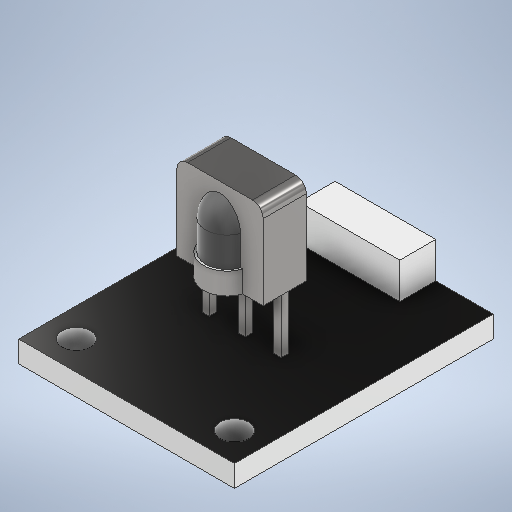
# Autodesk Inventor part: IR리모트 수광겐서
Saved by Autodesk Inventor 2025.3 (Build 293356030, 356C)
## iProperties
Created: 2025-09-11
Part Number: IR리모트 수광겐서
Material: ABS 플라스틱
Document SubType Name: Modeling
Designer: work
Density: 1.06 g/cm^3
Appearance: 매끄러움 - 흰색
Author: work
Autodesk Inventor part; units mm, degrees
ref_plane "YZ Plane" through (0, 0, 0) normal (1, 0, 0) x (0, 1, 0)
ref_plane "XZ Plane" through (0, 0, 0) normal (0, 1, 0) x (-1, 0, 0)
sketch "스케치1" plane through (0, 0, 0) normal (0, 1, 0) x (-1, 0, 0)
  line L0 (0, 0) -> (15, 0)
  line L1 (15, 0) -> (15, -18)
  line L2 (15, -18) -> (0, -18)
  line L3 (0, -18) -> (0, 0)
  dimension "d0" = 15
  dimension "d1" = 18
  constraints: 8 end point, 2 parallel, 1 horizontal, 1 perpendicular
  measures "d0" distance of L1.end L2.end
  measures "d1" distance of L0.end L1.end
extrude "돌출1" add sketch "스케치1" along normal blind 1.5
sketch "스케치2" plane through (0, 1.5, 0) normal (0, 1, 0) x (1, 0, 0)
  line L0 (-11, 15.5) -> (-4, 15.5)
  line L1 (-4, 15.5) -> (-4, 18)
  line L2 (-4, 18) -> (-11, 18)
  line L3 (-11, 18) -> (-11, 15.5)
  line L4 (0, 18) -> (-15, 18) projected
  point P0 (0, 0)
  point P1 (-7.5, 18)
  dimension "d4" = 7
  dimension "d5" = 2.5
  constraints: 8 end point, 2 midpoint, 2 parallel, 1 horizontal, 1 perpendicular
  measures "d4" distance of L2.end L1.end
  measures "d5" distance of L1.end L0.end
extrude "돌출2" add sketch "스케치2" along normal blind 2.5
sketch "스케치3" plane through (0, 1.5, 0) normal (0, 1, 0) x (1, 0, 0)
  line L0 (-10.25, 8) -> (-4.75, 8)
  line L1 (-4.75, 8) -> (-4.75, 8.5)
  line L2 (-4.75, 8.5) -> (-10.25, 8.5)
  line L3 (-10.25, 8.5) -> (-10.25, 8)
  line L4 (-15, 0) -> (0, 0) projected
  line L5 (-4, 18) -> (-11, 18) projected
  line L6 (-7.5, 18) -> (-7.5, 0) construction
  line L7 (-9.75, 8) -> (-9.75, 8.5)
  line L8 (-7.75, 8) -> (-7.75, 8.5)
  line L9 (-5.25, 8) -> (-5.25, 8.5)
  line L10 (-7.25, 8) -> (-7.25, 8.5)
  point P0 (-7.5, 8)
  point P1 (-4.75, 8.25)
  point P2 (-10.25, 8.25)
  dimension "d8" = 8
  dimension "d9" = 0.5
  dimension "d10" = 0.25
  dimension "d11" = 0.5
  dimension "d12" = 5.5
  constraints: 18 end point, 5 midpoint, 5 point on line, 4 symmetric about line, 3 perpendicular, 2 parallel, 1 horizontal
  measures "d8" distance between parallel lines of L4 L0
  measures "d9" distance of L2.end L0.start
  measures "d10" distance between parallel lines of L6 L8
  measures "d11" distance between parallel lines of L3 L7
  measures "d12" distance of point (-4.75, 8.25) point (-10.25, 8.25)
extrude "돌출3" add sketch "스케치3" along normal blind 4 contours L3 L2 L7 L0 | L8 L2 L10 L0 | L9 L2 L1 L0
sketch "스케치4" plane through (0, 5.5, 0) normal (0, 1, 0) x (1, 0, 0)
  line L0 (-10.5, 9.5) -> (-4.5, 9.5)
  line L1 (-4.5, 9.5) -> (-4.5, 6.5)
  line L2 (-4.5, 6.5) -> (-10.5, 6.5)
  line L3 (-10.5, 6.5) -> (-10.5, 9.5)
  line L4 (0, 18) -> (-15, 18) projected
  line L5 (-7.5, 18) -> (-7.5, 0) construction
  line L6 (-15, 0) -> (0, 0) projected
  line L7 (-7.25, 8.5) -> (-7.75, 8.5) projected
  point P0 (-7.5, 9.5)
  dimension "d15" = 6
  dimension "d16" = 3
  dimension "d17" = 1
  constraints: 10 end point, 3 midpoint, 2 parallel, 1 horizontal, 1 perpendicular, 1 point on line
  measures "d15" distance of L1.end L2.end
  measures "d16" distance of L0.end L1.end
  measures "d17" distance between parallel lines of L0 L7
extrude "돌출4" add sketch "스케치4" along normal blind 6
ref_plane "작업 평면1" through (-7.5, 5.5, -6.5) normal (1, 0, 0) x (0, 0, -1)
sketch "스케치5" plane through (-7.5, 5.5, -6.5) normal (1, 0, 0) x (0, 0, -1)
  line L0 (0, 0) -> (3, 0) projected
  line L1 (0.5, 0) -> (0.5, 5.5)
  arc A0 (0.5, 5.5) -> (-1, 3.5635) centre (1, 3.5635) ccw
  line L2 (-1, 3.5635) -> (-1, 0)
  line L3 (-1, 0) -> (0.5, 0)
  line L4 (3, 6) -> (0, 6) projected
  line L5 (0, 0) -> (0, 6) projected
  point P0 (-6.5, -5.5)
  point P1 (0, 5.2956)
  dimension "d21" = 0.5
  dimension "d22" = 1
  dimension "d23" = 2
  dimension "d24" = 0.5
  constraints: 6 end point, 2 point on circle, 2 vertical, 1 centre point, 1 collinear, 1 point on line, 1 tangent
  measures "d21" distance from line of L4 L1.end
  measures "d22" distance between parallel lines of L5 L2
  measures "d23" radius of A0
  measures "d24" distance between parallel lines of L5 L1
revolve "회전1" add sketch "스케치5" angle 360 about axis through (-7.5, 5.5, -7) along (0, 1, 0) contours L3 L2 A0 L5
sketch "스케치6" plane through (0, 5.5, 0) normal (0, -1, 0) x (1, 0, 0)
  arc A0 (-6.0858, -6.5) -> (-8.9142, -6.5) centre (-7.5, -7) ccw projected
  circle A1 centre (-7.5, -7) radius 1.65
  line L0 (-7.25, -8) -> (-7.25, -8.5) projected
  line L1 (-7.25, -8.5) -> (-7.5, -8.5) projected
  line L2 (-7.5, -8.5) -> (-7.75, -8.5) projected
  line L3 (-7.75, -8.5) -> (-7.75, -8) projected
  line L4 (-7.75, -8) -> (-7.25, -8) projected
  arc A2 (-6.0858, -6.5) -> (-8.9142, -6.5) centre (-7.5, -7) ccw projected
  line L5 (-10.5, -6.5) -> (-8.9142, -6.5) projected
  line L6 (-10.5, -9.5) -> (-10.5, -6.5) projected
  line L7 (-4.5, -9.5) -> (-10.5, -9.5) projected
  line L8 (-4.5, -6.5) -> (-4.5, -9.5) projected
  line L9 (-6.0858, -6.5) -> (-4.5, -6.5) projected
  line L10 (-10.25, -8.5) -> (-10.25, -8) projected
  line L11 (-10.25, -8) -> (-9.75, -8) projected
  line L12 (-9.75, -8) -> (-9.75, -8.5) projected
  line L13 (-9.75, -8.5) -> (-10.25, -8.5) projected
  line L14 (-4.75, -8) -> (-4.75, -8.5) projected
  line L15 (-4.75, -8.5) -> (-5.25, -8.5) projected
  line L16 (-5.25, -8.5) -> (-5.25, -8) projected
  line L17 (-5.25, -8) -> (-4.75, -8) projected
  point P0 (0, 0)
  point P1 (-6.0858, -6.5)
  point P2 (-5.9276, -6.5)
  point P3 (-9.0724, -6.5)
  dimension "d26" = 3.3
  constraints: 1 centre point, 1 coincident
  measures "d26" diameter of A1
extrude "돌출5" add sketch "스케치6" against normal blind 1.5 contours A0 L5 A1 L9 picked at (-7.6849, -5.4687)
fillet "모깎기1" radius 0.75 2 edges at (-4.5, 11.5, -8) (-10.5, 11.5, -8)
sketch "스케치7" plane through (0, 1.5, 0) normal (0, 1, 0) x (1, 0, 0)
  circle A0 centre (-2, 2) radius 1
  line L0 (-15, 0) -> (0, 0) projected
  line L1 (-7.5, 0) -> (-7.5, 2.0504)
  line L2 (0, 0) -> (0, 18) projected
  circle A1 centre (-13, 2) radius 1
  dimension "d30" = 2
  dimension "d31" = 2
  dimension "d32" = 2
  constraints: 2 centre point, 2 end point, 1 midpoint, 1 symmetric about line, 1 vertical, 1 other
  measures "d30" diameter of A0
  measures "d31" distance from line of L2 A0.centre
  measures "d32" distance from line of L0 A0.centre
extrude "돌출6" cut sketch "스케치7" against normal blind 1.5
